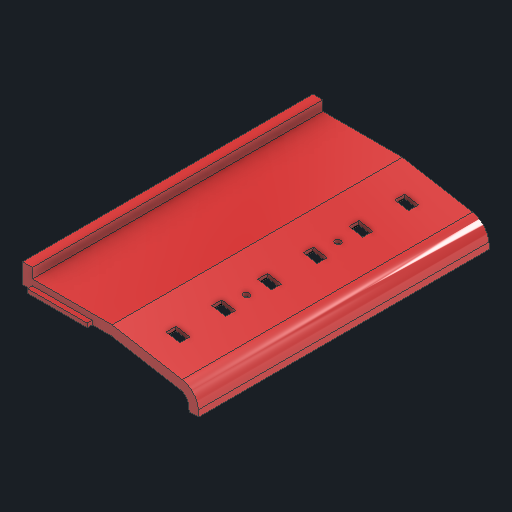
# Autodesk Inventor part: 7_5_2_toit_avant
Saved by Autodesk Inventor 2026 (Build 300175000, 175)
## iProperties
Created: 2025-06-21
Part Number: 7_5_2_toit_avant
Material: Generic
Document SubType Name: Modeling
Designer: remg9
Density: 1 g/cm^3
Appearance: Default
Author: remg9
Autodesk Inventor part; units mm, degrees
ref_plane "YZ Plane" through (0, 0, 0) normal (1, 0, 0) x (0, 1, 0)
ref_plane "XZ Plane" through (0, 0, 0) normal (0, 1, 0) x (-1, 0, 0)
ref_plane "XY Plane" through (0, 0, 0) normal (0, 0, 1) x (1, 0, 0)
sketch "Sketch5" plane through (0, 0, 0) normal (0, 0, 1) x (1, 0, 0)
  line L0 (0, 0) -> (0, -10)
  line L1 (0, -10) -> (44.5626, -10)
  line L2 (44.5626, -10) -> (79.3993, -16.1427)
  line L3 (0, 0) -> (5, 0)
  line L4 (5, 0) -> (5, -5)
  line L5 (5, -5) -> (45, -5)
  line L6 (45, -5) -> (80.2676, -11.2186) construction
  line L7 (45, -5) -> (96, -5) construction
  line L8 (96, -5) -> (96, -106) construction
  line L9 (96, -106) -> (88.493, -20.1951) construction
  arc A0 (88.493, -20.1951) -> (80.2676, -11.2186) centre (78.5311, -21.0667) ccw
  line L10 (85.4799, -43.1231) -> (83.5121, -20.6309) construction
  arc A1 (83.5121, -20.6309) -> (79.3993, -16.1427) centre (78.5311, -21.0667) ccw
  line L11 (83.7745, -23.6309) -> (88.7555, -23.1951)
  line L12 (88.493, -20.1951) -> (88.7555, -23.1951)
  line L13 (83.7745, -23.6309) -> (83.5121, -20.6309)
  line L14 (45, -5) -> (80.2676, -11.2186)
  dimension "d12" = 5
  dimension "d13" = 10
  dimension "d14" = 5
  dimension "d15" = 40
  dimension "d16" = 51
  dimension "d17" = 101
  dimension "d18" = 10
  dimension "d19" = 5
  dimension "d20" = 10
  dimension "d22" = 5
  dimension "d23" = 5
  dimension "d24" = 3
  constraints: 30 end point, 6 perpendicular, 4 point on circle, 4 tangent, 2 centre point, 2 horizontal, 2 point on line, 1 coincident, 1 collinear, 1 parallel, 1 vertical
  measures "d12" distance of L0.start L3.end
  measures "d13" distance of L0.start L0.end
  measures "d14" distance of L3.end L4.end
  measures "d15" distance of L4.end L5.end
  measures "d16" distance of L5.end L7.end
  measures "d17" distance of L7.end L8.end
  measures "d18" angle of L6 L7
  measures "d19" angle of L8 L9
  measures "d20" radius of A0
  measures "d22" distance between parallel lines of L2 L6
  measures "d23" distance between parallel lines of L9 L10
  measures "d24" vertical distance of L9.end L11.end
extrude "Extrusion3" add sketch "Sketch5" along normal blind 146
sketch "Sketch6" plane through (45, -5, 146) normal (0.1736482, 0.9848078, 0) x (0.9848078, -0.1736482, 0)
  line L0 (17.9058, 0) -> (17.9058, 146) construction
  line L1 (35.8116, 146) -> (0, 146) construction
  line L2 (35.8116, 0) -> (0, 0) construction
  circle A0 centre (17.9058, 50) radius 1.5
  line L3 (0, 73) -> (35.8116, 73) construction
  line L4 (35.8116, 146) -> (35.8116, 0) construction
  line L5 (0, 146) -> (0, 0) construction
  line L6 (14.4058, 59) -> (21.4058, 59)
  line L7 (21.4058, 59) -> (21.4058, 64)
  line L8 (21.4058, 64) -> (14.4058, 64)
  line L9 (14.4058, 64) -> (14.4058, 59)
  line L10 (14.4058, 36) -> (21.4058, 36)
  line L11 (21.4058, 36) -> (21.4058, 41)
  line L12 (21.4058, 41) -> (14.4058, 41)
  line L13 (14.4058, 41) -> (14.4058, 36)
  line L14 (14.4058, 13) -> (21.4058, 13)
  line L15 (21.4058, 13) -> (21.4058, 18)
  line L16 (21.4058, 18) -> (14.4058, 18)
  line L17 (14.4058, 18) -> (14.4058, 13)
  circle A1 centre (17.9058, 96) radius 1.5
  line L18 (14.4058, 87) -> (21.4058, 87)
  line L19 (21.4058, 87) -> (21.4058, 82)
  line L20 (21.4058, 82) -> (14.4058, 82)
  line L21 (14.4058, 82) -> (14.4058, 87)
  line L22 (14.4058, 110) -> (21.4058, 110)
  line L23 (21.4058, 110) -> (21.4058, 105)
  line L24 (21.4058, 105) -> (14.4058, 105)
  line L25 (14.4058, 105) -> (14.4058, 110)
  line L26 (14.4058, 133) -> (21.4058, 133)
  line L27 (21.4058, 133) -> (21.4058, 128)
  line L28 (21.4058, 128) -> (14.4058, 128)
  line L29 (14.4058, 128) -> (14.4058, 133)
  point P0 (-45.1846, 146)
  point P1 (17.9058, 64)
  point P2 (14.4058, 61.5)
  point P3 (17.9058, 41)
  point P4 (14.4058, 38.5)
  point P5 (17.9058, 18)
  point P6 (14.4058, 15.5)
  point P7 (17.9058, 82)
  point P8 (14.4058, 84.5)
  point P9 (17.9058, 105)
  point P10 (14.4058, 107.5)
  point P11 (17.9058, 128)
  point P12 (14.4058, 130.5)
  dimension "d27" = 23
  dimension "d28" = 3
  dimension "d29" = 5
  dimension "d30" = 7
  dimension "d31" = 11.5
  dimension "d32" = 5
  dimension "d33" = 7
  dimension "d34" = 5
  dimension "d35" = 7
  dimension "d36" = 23
  dimension "d37" = 23
  constraints: 52 end point, 19 symmetric about line, 10 midpoint, 6 parallel, 4 horizontal, 4 point on line, 3 perpendicular, 2 centre point, 1 vertical, 1 other
  measures "d27" distance from line of L3 A0.centre
  measures "d28" diameter of A0
  measures "d29" distance of L8.end L6.start
  measures "d30" distance of L7.end L8.end
  measures "d31" distance from line of L3 point (14.406, 61.5)
  measures "d32" distance of L12.end L10.start
  measures "d33" distance of L11.end L12.end
  measures "d34" distance of L16.end L14.start
  measures "d35" distance of L15.end L16.end
  measures "d36" distance of point (14.406, 61.5) point (14.406, 38.5)
  measures "d37" distance of point (14.406, 38.5) point (14.406, 15.5)
extrude "Extrusion4" cut sketch "Sketch6" against normal through all
sketch "Sketch7" plane through (79.3993, -16.1427, 0) normal (-0.1736482, -0.9848078, 0) x (0.9848078, -0.1736482, 0)
  line L0 (-23.1871, 143) -> (-12.1871, 143)
  line L1 (-12.1871, 143) -> (-12.1871, 3)
  line L2 (-12.1871, 3) -> (-23.1871, 3)
  line L3 (-23.1871, 3) -> (-23.1871, 143)
  line L4 (-17.6871, 146) -> (-17.6871, 0) construction
  line L5 (-35.3742, 146) -> (0, 146) construction
  line L6 (-35.3742, 0) -> (0, 0) construction
  point P0 (-80.9962, 0)
  point P1 (-17.6871, 3)
  dimension "d40" = 11
  dimension "d41" = 3
  dimension "d42" = 3
  constraints: 10 end point, 3 midpoint, 2 parallel, 1 horizontal, 1 perpendicular, 1 point on line, 1 vertical
  measures "d40" distance of L1.end L2.end
  measures "d41" distance between parallel lines of L6 L2
  measures "d42" distance between parallel lines of L5 L0
extrude "Extrusion5" cut sketch "Sketch7" against normal blind 3
sketch "Sketch8" plane through (0, 0, 146) normal (0, 0, 1) x (1, 0, 0)
  line L0 (5, -8) -> (35, -8)
  line L1 (35, -8) -> (35, -10)
  line L2 (35, -10) -> (5, -10)
  line L3 (5, -10) -> (5, -8)
  line L4 (0, -10) -> (44.5626, -10) projected
  line L5 (5, -5) -> (5, 0) projected
  point P0 (0, 0)
  dimension "d45" = 2
  dimension "d46" = 30
  constraints: 8 end point, 2 collinear, 2 parallel, 1 horizontal, 1 perpendicular
  measures "d45" distance of L2.end L0.start
  measures "d46" distance of L0.start L0.end
extrude "Extrusion6" add sketch "Sketch8" along normal blind 2.5 and the other way blind 148.5
body "Solid2"
